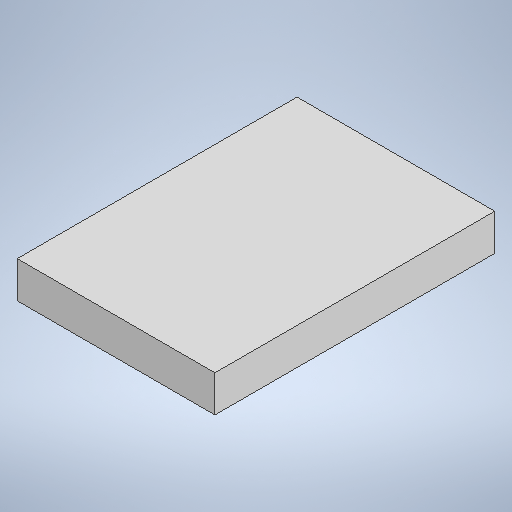
# Autodesk Inventor part: proto
Saved by Autodesk Inventor 2025.3 (Build 293356030, 356C)
## iProperties
Created: 2026-05-06
Part Number: proto
Material: Generic
Document SubType Name: Modeling
Designer: pablo
Density: 1 g/cm^3
Appearance: Default
Author: pablo
Autodesk Inventor part; units mm, degrees
ref_plane "YZ Plane" through (0, 0, 0) normal (1, 0, 0) x (0, 1, 0)
ref_plane "XZ Plane" through (0, 0, 0) normal (0, 1, 0) x (-1, 0, 0)
ref_plane "XY Plane" through (0, 0, 0) normal (0, 0, 1) x (1, 0, 0)
sketch "Sketch1" plane through (0, 0, 0) normal (0, 1, 0) x (-1, 0, 0)
  line L0 (0, 0) -> (61, 0)
  line L1 (61, 0) -> (61, -88)
  line L2 (61, -88) -> (0, -88)
  line L3 (0, -88) -> (0, 0)
  line L4 (63, 2) -> (-2, 2)
  line L5 (-2, 2) -> (-2, -90)
  line L6 (-2, -90) -> (63, -90)
  line L7 (63, -90) -> (63, 2)
  dimension "d0" = 88
  dimension "d1" = 61
  dimension "d2" = 2
  dimension "d3" = 2
  dimension "d4" = 2
  dimension "d5" = 2
  dimension "d10" = 65
  dimension "d11" = 92
  constraints: 16 end point, 4 parallel, 2 horizontal, 2 perpendicular
  measures "d0" distance of L2.end L0.start
  measures "d1" distance of L1.end L2.end
  measures "d2" distance between parallel lines of L5 L3
  measures "d3" distance between parallel lines of L4 L0
  measures "d4" distance between parallel lines of L1 L7
  measures "d5" distance between parallel lines of L6 L2
  measures "d10" distance between parallel lines of L7 L5
  measures "d11" distance between parallel lines of L4 L6
extrude "Extrusion1" add sketch "Sketch1" along normal blind 3 contours L0 L1 L2 L3 | L7 L6 L5 L4
sketch "Sketch2" plane through (0, 0, 0) normal (0, -1, 0) x (1, 0, 0)
  line L0 (0, -88) -> (0, 0) projected
  line L1 (2, 2) -> (2, -90) projected
  line L2 (2, 2) -> (2, -90) projected
  line L3 (2, -90) -> (-63, -90) projected
  line L4 (2, -90) -> (-63, -90) projected
  line L5 (-63, -90) -> (-63, 2) projected
  line L6 (-63, -90) -> (-63, 2) projected
  line L7 (-63, 2) -> (2, 2) projected
  line L8 (-63, 2) -> (2, 2) projected
  line L9 (2, 2) -> (2, -90) projected
  line L10 (-63, 2) -> (2, 2) projected
  line L11 (-63, -90) -> (-63, 2) projected
  line L12 (2, -90) -> (-63, -90) projected
  line L13 (2, 2) -> (2, -90) projected
  line L14 (2, -90) -> (-63, -90) projected
  line L15 (-63, -90) -> (-63, 2) projected
  line L16 (-63, 2) -> (2, 2) projected
  line L17 (2, 2) -> (2, -90) projected
  line L18 (2, 2) -> (2, -90) projected
  line L19 (2, -90) -> (-63, -90) projected
  line L20 (2, -90) -> (-63, -90) projected
  line L21 (-63, -90) -> (-63, 2) projected
  line L22 (-63, -90) -> (-63, 2) projected
  line L23 (-63, 2) -> (2, 2) projected
  line L24 (-63, 2) -> (2, 2) projected
  line L25 (0, 0) -> (-61, 0) projected
  line L26 (-61, 0) -> (-61, -88) projected
  line L27 (-61, -88) -> (0, -88) projected
  line L28 (-63, 2) -> (2, 2) projected
  line L29 (2, 2) -> (2, -90) projected
  line L30 (2, -90) -> (-63, -90) projected
  line L31 (-63, -90) -> (-63, 2) projected
  constraints: 4 other
extrude "Extrusion2" add sketch "Sketch2" along normal blind 9
body "Solid1"
